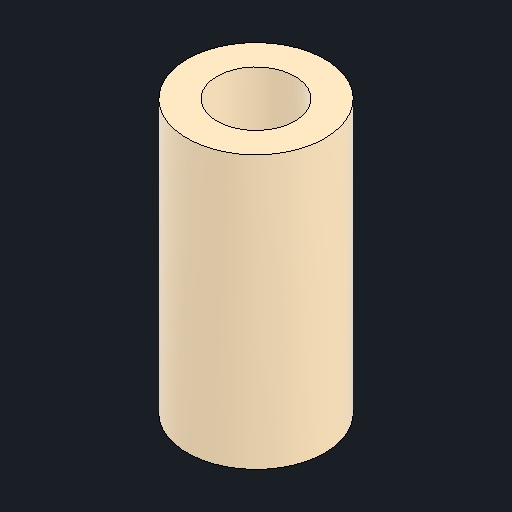
# Autodesk Inventor part: Ceramics-spacer
Saved by Autodesk Inventor 2027.1 (Build 311270010, 270A)
## iProperties
Created: 2026-08-19
Part Number: Ceramics-spacer
Material: 窒化ケイ素
Document SubType Name: Modeling
Designer: rkawa
Density: 3.18 g/cm^3
Appearance: 滑らか - オフホワイト
Mass: 0.500625 g
Surface Area: 3.03776 cm^2
Volume: 0.157429 cm^3
Author: rkawa
Autodesk Inventor part; units mm, degrees
ref_plane "YZ Plane" through (0, 0, 0) normal (1, 0, 0) x (0, 1, 0)
ref_plane "XZ Plane" through (0, 0, 0) normal (0, 1, 0) x (-1, 0, 0)
ref_plane "XY Plane" through (0, 0, 0) normal (0, 0, 1) x (1, 0, 0)
sketch "スケッチ1" plane through (0, 0, 0) normal (0, 1, 0) x (-1, 0, 0)
  circle A0 centre (0, 0) radius 2.65
  circle A1 centre (0, 0) radius 1.5
  dimension "d0" = 5.3
  dimension "d1" = 3
  constraints: 2 centre point, 2 coincident
  measures "d0" diameter of A0
  measures "d1" diameter of A1
extrude "押し出し1" add sketch "スケッチ1" along normal blind 10.5
